Autodesk Fusion 360 part; units mm, degrees
(part 2 of 2)
ref_plane "WorkPlane5" through (0, 0, 7.4) normal (0, 0, 1) x (1, 0, 0) in component "07 Spar fit coupon - 4.1 4.3 4.4 4.5 4.7"
sketch "Label 4.1 digit 0 c sketch" plane through (0, 0, 7.4) normal (0, 0, 1) x (1, 0, 0) in component "07 Spar fit coupon - 4.1 4.3 4.4 4.5 4.7"
  line L0 (9.5, 4.95) -> (9.8, 4.95)
  line L1 (9.8, 4.95) -> (9.8, 5.85)
  line L2 (9.8, 5.85) -> (9.5, 5.85)
  line L3 (9.5, 5.85) -> (9.5, 4.95)
extrude "Label 4.1 digit 0 c" cut sketch "Label 4.1 digit 0 c sketch" along normal blind 1 bodies 7 in component "07 Spar fit coupon - 4.1 4.3 4.4 4.5 4.7"
ref_plane "WorkPlane6" through (0, 0, 7.4) normal (0, 0, 1) x (1, 0, 0) in component "07 Spar fit coupon - 4.1 4.3 4.4 4.5 4.7"
sketch "Label 4.1 dot sketch" plane through (0, 0, 7.4) normal (0, 0, 1) x (1, 0, 0) in component "07 Spar fit coupon - 4.1 4.3 4.4 4.5 4.7"
  line L0 (10.5, 4.5) -> (10.85, 4.5)
  line L1 (10.85, 4.5) -> (10.85, 4.85)
  line L2 (10.85, 4.85) -> (10.5, 4.85)
  line L3 (10.5, 4.85) -> (10.5, 4.5)
extrude "Label 4.1 dot" cut sketch "Label 4.1 dot sketch" along normal blind 1 bodies 7 in component "07 Spar fit coupon - 4.1 4.3 4.4 4.5 4.7"
ref_plane "WorkPlane7" through (0, 0, 7.4) normal (0, 0, 1) x (1, 0, 0) in component "07 Spar fit coupon - 4.1 4.3 4.4 4.5 4.7"
sketch "Label 4.1 digit 2 b sketch" plane through (0, 0, 7.4) normal (0, 0, 1) x (1, 0, 0) in component "07 Spar fit coupon - 4.1 4.3 4.4 4.5 4.7"
  line L0 (14.5, 6.15) -> (14.8, 6.15)
  line L1 (14.8, 6.15) -> (14.8, 7.05)
  line L2 (14.8, 7.05) -> (14.5, 7.05)
  line L3 (14.5, 7.05) -> (14.5, 6.15)
extrude "Label 4.1 digit 2 b" cut sketch "Label 4.1 digit 2 b sketch" along normal blind 1 bodies 7 in component "07 Spar fit coupon - 4.1 4.3 4.4 4.5 4.7"
ref_plane "WorkPlane8" through (0, 0, 7.4) normal (0, 0, 1) x (1, 0, 0) in component "07 Spar fit coupon - 4.1 4.3 4.4 4.5 4.7"
sketch "Label 4.1 digit 2 c sketch" plane through (0, 0, 7.4) normal (0, 0, 1) x (1, 0, 0) in component "07 Spar fit coupon - 4.1 4.3 4.4 4.5 4.7"
  line L0 (14.5, 4.95) -> (14.8, 4.95)
  line L1 (14.8, 4.95) -> (14.8, 5.85)
  line L2 (14.8, 5.85) -> (14.5, 5.85)
  line L3 (14.5, 5.85) -> (14.5, 4.95)
extrude "Label 4.1 digit 2 c" cut sketch "Label 4.1 digit 2 c sketch" along normal blind 1 bodies 7 in component "07 Spar fit coupon - 4.1 4.3 4.4 4.5 4.7"
ref_plane "WorkPlane9" through (-0.05, 0, 0) normal (1, 0, 0) x (0, 1, 0) in component "07 Spar fit coupon - 4.1 4.3 4.4 4.5 4.7"
sketch "Horizontal 4.3 mm fit bore sketch" plane through (-0.05, 0, 0) normal (1, 0, 0) x (0, 0, -1) in component "07 Spar fit coupon - 4.1 4.3 4.4 4.5 4.7"
  circle A0 centre (-3.5, 18) radius 2.15
extrude "Horizontal 4.3 mm fit bore" cut sketch "Horizontal 4.3 mm fit bore sketch" along normal blind 24.1 bodies 7 in component "07 Spar fit coupon - 4.1 4.3 4.4 4.5 4.7"
ref_plane "WorkPlane10" through (0, 0, 7.4) normal (0, 0, 1) x (1, 0, 0) in component "07 Spar fit coupon - 4.1 4.3 4.4 4.5 4.7"
sketch "Label 4.3 digit 0 f sketch" plane through (0, 0, 7.4) normal (0, 0, 1) x (1, 0, 0) in component "07 Spar fit coupon - 4.1 4.3 4.4 4.5 4.7"
  line L0 (8, 18.15) -> (8.3, 18.15)
  line L1 (8.3, 18.15) -> (8.3, 19.05)
  line L2 (8.3, 19.05) -> (8, 19.05)
  line L3 (8, 19.05) -> (8, 18.15)
extrude "Label 4.3 digit 0 f" cut sketch "Label 4.3 digit 0 f sketch" along normal blind 1 bodies 7 in component "07 Spar fit coupon - 4.1 4.3 4.4 4.5 4.7"
ref_plane "WorkPlane11" through (0, 0, 7.4) normal (0, 0, 1) x (1, 0, 0) in component "07 Spar fit coupon - 4.1 4.3 4.4 4.5 4.7"
sketch "Label 4.3 digit 0 g sketch" plane through (0, 0, 7.4) normal (0, 0, 1) x (1, 0, 0) in component "07 Spar fit coupon - 4.1 4.3 4.4 4.5 4.7"
  line L0 (8, 17.85) -> (9.8, 17.85)
  line L1 (9.8, 17.85) -> (9.8, 18.15)
  line L2 (9.8, 18.15) -> (8, 18.15)
  line L3 (8, 18.15) -> (8, 17.85)
extrude "Label 4.3 digit 0 g" cut sketch "Label 4.3 digit 0 g sketch" along normal blind 1 bodies 7 in component "07 Spar fit coupon - 4.1 4.3 4.4 4.5 4.7"
ref_plane "WorkPlane12" through (0, 0, 7.4) normal (0, 0, 1) x (1, 0, 0) in component "07 Spar fit coupon - 4.1 4.3 4.4 4.5 4.7"
sketch "Label 4.3 digit 0 b sketch" plane through (0, 0, 7.4) normal (0, 0, 1) x (1, 0, 0) in component "07 Spar fit coupon - 4.1 4.3 4.4 4.5 4.7"
  line L0 (9.5, 18.15) -> (9.8, 18.15)
  line L1 (9.8, 18.15) -> (9.8, 19.05)
  line L2 (9.8, 19.05) -> (9.5, 19.05)
  line L3 (9.5, 19.05) -> (9.5, 18.15)
extrude "Label 4.3 digit 0 b" cut sketch "Label 4.3 digit 0 b sketch" along normal blind 1 bodies 7 in component "07 Spar fit coupon - 4.1 4.3 4.4 4.5 4.7"
ref_plane "WorkPlane13" through (0, 0, 7.4) normal (0, 0, 1) x (1, 0, 0) in component "07 Spar fit coupon - 4.1 4.3 4.4 4.5 4.7"
sketch "Label 4.3 digit 0 c sketch" plane through (0, 0, 7.4) normal (0, 0, 1) x (1, 0, 0) in component "07 Spar fit coupon - 4.1 4.3 4.4 4.5 4.7"
  line L0 (9.5, 16.95) -> (9.8, 16.95)
  line L1 (9.8, 16.95) -> (9.8, 17.85)
  line L2 (9.8, 17.85) -> (9.5, 17.85)
  line L3 (9.5, 17.85) -> (9.5, 16.95)
extrude "Label 4.3 digit 0 c" cut sketch "Label 4.3 digit 0 c sketch" along normal blind 1 bodies 7 in component "07 Spar fit coupon - 4.1 4.3 4.4 4.5 4.7"
ref_plane "WorkPlane14" through (0, 0, 7.4) normal (0, 0, 1) x (1, 0, 0) in component "07 Spar fit coupon - 4.1 4.3 4.4 4.5 4.7"
sketch "Label 4.3 dot sketch" plane through (0, 0, 7.4) normal (0, 0, 1) x (1, 0, 0) in component "07 Spar fit coupon - 4.1 4.3 4.4 4.5 4.7"
  line L0 (10.5, 16.5) -> (10.85, 16.5)
  line L1 (10.85, 16.5) -> (10.85, 16.85)
  line L2 (10.85, 16.85) -> (10.5, 16.85)
  line L3 (10.5, 16.85) -> (10.5, 16.5)
extrude "Label 4.3 dot" cut sketch "Label 4.3 dot sketch" along normal blind 1 bodies 7 in component "07 Spar fit coupon - 4.1 4.3 4.4 4.5 4.7"
ref_plane "WorkPlane15" through (0, 0, 7.4) normal (0, 0, 1) x (1, 0, 0) in component "07 Spar fit coupon - 4.1 4.3 4.4 4.5 4.7"
sketch "Label 4.3 digit 2 a sketch" plane through (0, 0, 7.4) normal (0, 0, 1) x (1, 0, 0) in component "07 Spar fit coupon - 4.1 4.3 4.4 4.5 4.7"
  line L0 (13, 19.2) -> (14.8, 19.2)
  line L1 (14.8, 19.2) -> (14.8, 19.5)
  line L2 (14.8, 19.5) -> (13, 19.5)
  line L3 (13, 19.5) -> (13, 19.2)
extrude "Label 4.3 digit 2 a" cut sketch "Label 4.3 digit 2 a sketch" along normal blind 1 bodies 7 in component "07 Spar fit coupon - 4.1 4.3 4.4 4.5 4.7"
ref_plane "WorkPlane16" through (0, 0, 7.4) normal (0, 0, 1) x (1, 0, 0) in component "07 Spar fit coupon - 4.1 4.3 4.4 4.5 4.7"
sketch "Label 4.3 digit 2 b sketch" plane through (0, 0, 7.4) normal (0, 0, 1) x (1, 0, 0) in component "07 Spar fit coupon - 4.1 4.3 4.4 4.5 4.7"
  line L0 (14.5, 18.15) -> (14.8, 18.15)
  line L1 (14.8, 18.15) -> (14.8, 19.05)
  line L2 (14.8, 19.05) -> (14.5, 19.05)
  line L3 (14.5, 19.05) -> (14.5, 18.15)
extrude "Label 4.3 digit 2 b" cut sketch "Label 4.3 digit 2 b sketch" along normal blind 1 bodies 7 in component "07 Spar fit coupon - 4.1 4.3 4.4 4.5 4.7"
ref_plane "WorkPlane17" through (0, 0, 7.4) normal (0, 0, 1) x (1, 0, 0) in component "07 Spar fit coupon - 4.1 4.3 4.4 4.5 4.7"
sketch "Label 4.3 digit 2 g sketch" plane through (0, 0, 7.4) normal (0, 0, 1) x (1, 0, 0) in component "07 Spar fit coupon - 4.1 4.3 4.4 4.5 4.7"
  line L0 (13, 17.85) -> (14.8, 17.85)
  line L1 (14.8, 17.85) -> (14.8, 18.15)
  line L2 (14.8, 18.15) -> (13, 18.15)
  line L3 (13, 18.15) -> (13, 17.85)
extrude "Label 4.3 digit 2 g" cut sketch "Label 4.3 digit 2 g sketch" along normal blind 1 bodies 7 in component "07 Spar fit coupon - 4.1 4.3 4.4 4.5 4.7"
ref_plane "WorkPlane18" through (0, 0, 7.4) normal (0, 0, 1) x (1, 0, 0) in component "07 Spar fit coupon - 4.1 4.3 4.4 4.5 4.7"
sketch "Label 4.3 digit 2 c sketch" plane through (0, 0, 7.4) normal (0, 0, 1) x (1, 0, 0) in component "07 Spar fit coupon - 4.1 4.3 4.4 4.5 4.7"
  line L0 (14.5, 16.95) -> (14.8, 16.95)
  line L1 (14.8, 16.95) -> (14.8, 17.85)
  line L2 (14.8, 17.85) -> (14.5, 17.85)
  line L3 (14.5, 17.85) -> (14.5, 16.95)
extrude "Label 4.3 digit 2 c" cut sketch "Label 4.3 digit 2 c sketch" along normal blind 1 bodies 7 in component "07 Spar fit coupon - 4.1 4.3 4.4 4.5 4.7"
ref_plane "WorkPlane19" through (0, 0, 7.4) normal (0, 0, 1) x (1, 0, 0) in component "07 Spar fit coupon - 4.1 4.3 4.4 4.5 4.7"
sketch "Label 4.3 digit 2 d sketch" plane through (0, 0, 7.4) normal (0, 0, 1) x (1, 0, 0) in component "07 Spar fit coupon - 4.1 4.3 4.4 4.5 4.7"
  line L0 (13, 16.5) -> (14.8, 16.5)
  line L1 (14.8, 16.5) -> (14.8, 16.8)
  line L2 (14.8, 16.8) -> (13, 16.8)
  line L3 (13, 16.8) -> (13, 16.5)
extrude "Label 4.3 digit 2 d" cut sketch "Label 4.3 digit 2 d sketch" along normal blind 1 bodies 7 in component "07 Spar fit coupon - 4.1 4.3 4.4 4.5 4.7"
ref_plane "WorkPlane20" through (-0.05, 0, 0) normal (1, 0, 0) x (0, 1, 0) in component "07 Spar fit coupon - 4.1 4.3 4.4 4.5 4.7"
sketch "Horizontal 4.4 mm fit bore sketch" plane through (-0.05, 0, 0) normal (1, 0, 0) x (0, 0, -1) in component "07 Spar fit coupon - 4.1 4.3 4.4 4.5 4.7"
  circle A0 centre (-3.5, 30) radius 2.2
extrude "Horizontal 4.4 mm fit bore" cut sketch "Horizontal 4.4 mm fit bore sketch" along normal blind 24.1 bodies 7 in component "07 Spar fit coupon - 4.1 4.3 4.4 4.5 4.7"
ref_plane "WorkPlane21" through (0, 0, 7.4) normal (0, 0, 1) x (1, 0, 0) in component "07 Spar fit coupon - 4.1 4.3 4.4 4.5 4.7"
sketch "Label 4.4 digit 0 f sketch" plane through (0, 0, 7.4) normal (0, 0, 1) x (1, 0, 0) in component "07 Spar fit coupon - 4.1 4.3 4.4 4.5 4.7"
  line L0 (8, 30.15) -> (8.3, 30.15)
  line L1 (8.3, 30.15) -> (8.3, 31.05)
  line L2 (8.3, 31.05) -> (8, 31.05)
  line L3 (8, 31.05) -> (8, 30.15)
extrude "Label 4.4 digit 0 f" cut sketch "Label 4.4 digit 0 f sketch" along normal blind 1 bodies 7 in component "07 Spar fit coupon - 4.1 4.3 4.4 4.5 4.7"
ref_plane "WorkPlane22" through (0, 0, 7.4) normal (0, 0, 1) x (1, 0, 0) in component "07 Spar fit coupon - 4.1 4.3 4.4 4.5 4.7"
sketch "Label 4.4 digit 0 g sketch" plane through (0, 0, 7.4) normal (0, 0, 1) x (1, 0, 0) in component "07 Spar fit coupon - 4.1 4.3 4.4 4.5 4.7"
  line L0 (8, 29.85) -> (9.8, 29.85)
  line L1 (9.8, 29.85) -> (9.8, 30.15)
  line L2 (9.8, 30.15) -> (8, 30.15)
  line L3 (8, 30.15) -> (8, 29.85)
extrude "Label 4.4 digit 0 g" cut sketch "Label 4.4 digit 0 g sketch" along normal blind 1 bodies 7 in component "07 Spar fit coupon - 4.1 4.3 4.4 4.5 4.7"
ref_plane "WorkPlane23" through (0, 0, 7.4) normal (0, 0, 1) x (1, 0, 0) in component "07 Spar fit coupon - 4.1 4.3 4.4 4.5 4.7"
sketch "Label 4.4 digit 0 b sketch" plane through (0, 0, 7.4) normal (0, 0, 1) x (1, 0, 0) in component "07 Spar fit coupon - 4.1 4.3 4.4 4.5 4.7"
  line L0 (9.5, 30.15) -> (9.8, 30.15)
  line L1 (9.8, 30.15) -> (9.8, 31.05)
  line L2 (9.8, 31.05) -> (9.5, 31.05)
  line L3 (9.5, 31.05) -> (9.5, 30.15)
extrude "Label 4.4 digit 0 b" cut sketch "Label 4.4 digit 0 b sketch" along normal blind 1 bodies 7 in component "07 Spar fit coupon - 4.1 4.3 4.4 4.5 4.7"
ref_plane "WorkPlane24" through (0, 0, 7.4) normal (0, 0, 1) x (1, 0, 0) in component "07 Spar fit coupon - 4.1 4.3 4.4 4.5 4.7"
sketch "Label 4.4 digit 0 c sketch" plane through (0, 0, 7.4) normal (0, 0, 1) x (1, 0, 0) in component "07 Spar fit coupon - 4.1 4.3 4.4 4.5 4.7"
  line L0 (9.5, 28.95) -> (9.8, 28.95)
  line L1 (9.8, 28.95) -> (9.8, 29.85)
  line L2 (9.8, 29.85) -> (9.5, 29.85)
  line L3 (9.5, 29.85) -> (9.5, 28.95)
extrude "Label 4.4 digit 0 c" cut sketch "Label 4.4 digit 0 c sketch" along normal blind 1 bodies 7 in component "07 Spar fit coupon - 4.1 4.3 4.4 4.5 4.7"
ref_plane "WorkPlane25" through (0, 0, 7.4) normal (0, 0, 1) x (1, 0, 0) in component "07 Spar fit coupon - 4.1 4.3 4.4 4.5 4.7"
sketch "Label 4.4 dot sketch" plane through (0, 0, 7.4) normal (0, 0, 1) x (1, 0, 0) in component "07 Spar fit coupon - 4.1 4.3 4.4 4.5 4.7"
  line L0 (10.5, 28.5) -> (10.85, 28.5)
  line L1 (10.85, 28.5) -> (10.85, 28.85)
  line L2 (10.85, 28.85) -> (10.5, 28.85)
  line L3 (10.5, 28.85) -> (10.5, 28.5)
extrude "Label 4.4 dot" cut sketch "Label 4.4 dot sketch" along normal blind 1 bodies 7 in component "07 Spar fit coupon - 4.1 4.3 4.4 4.5 4.7"
ref_plane "WorkPlane26" through (0, 0, 7.4) normal (0, 0, 1) x (1, 0, 0) in component "07 Spar fit coupon - 4.1 4.3 4.4 4.5 4.7"
sketch "Label 4.4 digit 2 f sketch" plane through (0, 0, 7.4) normal (0, 0, 1) x (1, 0, 0) in component "07 Spar fit coupon - 4.1 4.3 4.4 4.5 4.7"
  line L0 (13, 30.15) -> (13.3, 30.15)
  line L1 (13.3, 30.15) -> (13.3, 31.05)
  line L2 (13.3, 31.05) -> (13, 31.05)
  line L3 (13, 31.05) -> (13, 30.15)
extrude "Label 4.4 digit 2 f" cut sketch "Label 4.4 digit 2 f sketch" along normal blind 1 bodies 7 in component "07 Spar fit coupon - 4.1 4.3 4.4 4.5 4.7"
ref_plane "WorkPlane27" through (0, 0, 7.4) normal (0, 0, 1) x (1, 0, 0) in component "07 Spar fit coupon - 4.1 4.3 4.4 4.5 4.7"
sketch "Label 4.4 digit 2 g sketch" plane through (0, 0, 7.4) normal (0, 0, 1) x (1, 0, 0) in component "07 Spar fit coupon - 4.1 4.3 4.4 4.5 4.7"
  line L0 (13, 29.85) -> (14.8, 29.85)
  line L1 (14.8, 29.85) -> (14.8, 30.15)
  line L2 (14.8, 30.15) -> (13, 30.15)
  line L3 (13, 30.15) -> (13, 29.85)
extrude "Label 4.4 digit 2 g" cut sketch "Label 4.4 digit 2 g sketch" along normal blind 1 bodies 7 in component "07 Spar fit coupon - 4.1 4.3 4.4 4.5 4.7"
ref_plane "WorkPlane28" through (0, 0, 7.4) normal (0, 0, 1) x (1, 0, 0) in component "07 Spar fit coupon - 4.1 4.3 4.4 4.5 4.7"
sketch "Label 4.4 digit 2 b sketch" plane through (0, 0, 7.4) normal (0, 0, 1) x (1, 0, 0) in component "07 Spar fit coupon - 4.1 4.3 4.4 4.5 4.7"
  line L0 (14.5, 30.15) -> (14.8, 30.15)
  line L1 (14.8, 30.15) -> (14.8, 31.05)
  line L2 (14.8, 31.05) -> (14.5, 31.05)
  line L3 (14.5, 31.05) -> (14.5, 30.15)
extrude "Label 4.4 digit 2 b" cut sketch "Label 4.4 digit 2 b sketch" along normal blind 1 bodies 7 in component "07 Spar fit coupon - 4.1 4.3 4.4 4.5 4.7"
ref_plane "WorkPlane29" through (0, 0, 7.4) normal (0, 0, 1) x (1, 0, 0) in component "07 Spar fit coupon - 4.1 4.3 4.4 4.5 4.7"
sketch "Label 4.4 digit 2 c sketch" plane through (0, 0, 7.4) normal (0, 0, 1) x (1, 0, 0) in component "07 Spar fit coupon - 4.1 4.3 4.4 4.5 4.7"
  line L0 (14.5, 28.95) -> (14.8, 28.95)
  line L1 (14.8, 28.95) -> (14.8, 29.85)
  line L2 (14.8, 29.85) -> (14.5, 29.85)
  line L3 (14.5, 29.85) -> (14.5, 28.95)
extrude "Label 4.4 digit 2 c" cut sketch "Label 4.4 digit 2 c sketch" along normal blind 1 bodies 7 in component "07 Spar fit coupon - 4.1 4.3 4.4 4.5 4.7"
ref_plane "WorkPlane30" through (-0.05, 0, 0) normal (1, 0, 0) x (0, 1, 0) in component "07 Spar fit coupon - 4.1 4.3 4.4 4.5 4.7"
sketch "Horizontal 4.5 mm fit bore sketch" plane through (-0.05, 0, 0) normal (1, 0, 0) x (0, 0, -1) in component "07 Spar fit coupon - 4.1 4.3 4.4 4.5 4.7"
  circle A0 centre (-3.5, 42) radius 2.25
extrude "Horizontal 4.5 mm fit bore" cut sketch "Horizontal 4.5 mm fit bore sketch" along normal blind 24.1 bodies 7 in component "07 Spar fit coupon - 4.1 4.3 4.4 4.5 4.7"
ref_plane "WorkPlane31" through (0, 0, 7.4) normal (0, 0, 1) x (1, 0, 0) in component "07 Spar fit coupon - 4.1 4.3 4.4 4.5 4.7"
sketch "Label 4.5 digit 0 f sketch" plane through (0, 0, 7.4) normal (0, 0, 1) x (1, 0, 0) in component "07 Spar fit coupon - 4.1 4.3 4.4 4.5 4.7"
  line L0 (8, 42.15) -> (8.3, 42.15)
  line L1 (8.3, 42.15) -> (8.3, 43.05)
  line L2 (8.3, 43.05) -> (8, 43.05)
  line L3 (8, 43.05) -> (8, 42.15)
extrude "Label 4.5 digit 0 f" cut sketch "Label 4.5 digit 0 f sketch" along normal blind 1 bodies 7 in component "07 Spar fit coupon - 4.1 4.3 4.4 4.5 4.7"
ref_plane "WorkPlane32" through (0, 0, 7.4) normal (0, 0, 1) x (1, 0, 0) in component "07 Spar fit coupon - 4.1 4.3 4.4 4.5 4.7"
sketch "Label 4.5 digit 0 g sketch" plane through (0, 0, 7.4) normal (0, 0, 1) x (1, 0, 0) in component "07 Spar fit coupon - 4.1 4.3 4.4 4.5 4.7"
  line L0 (8, 41.85) -> (9.8, 41.85)
  line L1 (9.8, 41.85) -> (9.8, 42.15)
  line L2 (9.8, 42.15) -> (8, 42.15)
  line L3 (8, 42.15) -> (8, 41.85)
extrude "Label 4.5 digit 0 g" cut sketch "Label 4.5 digit 0 g sketch" along normal blind 1 bodies 7 in component "07 Spar fit coupon - 4.1 4.3 4.4 4.5 4.7"
ref_plane "WorkPlane33" through (0, 0, 7.4) normal (0, 0, 1) x (1, 0, 0) in component "07 Spar fit coupon - 4.1 4.3 4.4 4.5 4.7"
sketch "Label 4.5 digit 0 b sketch" plane through (0, 0, 7.4) normal (0, 0, 1) x (1, 0, 0) in component "07 Spar fit coupon - 4.1 4.3 4.4 4.5 4.7"
  line L0 (9.5, 42.15) -> (9.8, 42.15)
  line L1 (9.8, 42.15) -> (9.8, 43.05)
  line L2 (9.8, 43.05) -> (9.5, 43.05)
  line L3 (9.5, 43.05) -> (9.5, 42.15)
extrude "Label 4.5 digit 0 b" cut sketch "Label 4.5 digit 0 b sketch" along normal blind 1 bodies 7 in component "07 Spar fit coupon - 4.1 4.3 4.4 4.5 4.7"
ref_plane "WorkPlane34" through (0, 0, 7.4) normal (0, 0, 1) x (1, 0, 0) in component "07 Spar fit coupon - 4.1 4.3 4.4 4.5 4.7"
sketch "Label 4.5 digit 0 c sketch" plane through (0, 0, 7.4) normal (0, 0, 1) x (1, 0, 0) in component "07 Spar fit coupon - 4.1 4.3 4.4 4.5 4.7"
  line L0 (9.5, 40.95) -> (9.8, 40.95)
  line L1 (9.8, 40.95) -> (9.8, 41.85)
  line L2 (9.8, 41.85) -> (9.5, 41.85)
  line L3 (9.5, 41.85) -> (9.5, 40.95)
extrude "Label 4.5 digit 0 c" cut sketch "Label 4.5 digit 0 c sketch" along normal blind 1 bodies 7 in component "07 Spar fit coupon - 4.1 4.3 4.4 4.5 4.7"
ref_plane "WorkPlane35" through (0, 0, 7.4) normal (0, 0, 1) x (1, 0, 0) in component "07 Spar fit coupon - 4.1 4.3 4.4 4.5 4.7"
sketch "Label 4.5 dot sketch" plane through (0, 0, 7.4) normal (0, 0, 1) x (1, 0, 0) in component "07 Spar fit coupon - 4.1 4.3 4.4 4.5 4.7"
  line L0 (10.5, 40.5) -> (10.85, 40.5)
  line L1 (10.85, 40.5) -> (10.85, 40.85)
  line L2 (10.85, 40.85) -> (10.5, 40.85)
  line L3 (10.5, 40.85) -> (10.5, 40.5)
extrude "Label 4.5 dot" cut sketch "Label 4.5 dot sketch" along normal blind 1 bodies 7 in component "07 Spar fit coupon - 4.1 4.3 4.4 4.5 4.7"
ref_plane "WorkPlane36" through (0, 0, 7.4) normal (0, 0, 1) x (1, 0, 0) in component "07 Spar fit coupon - 4.1 4.3 4.4 4.5 4.7"
sketch "Label 4.5 digit 2 a sketch" plane through (0, 0, 7.4) normal (0, 0, 1) x (1, 0, 0) in component "07 Spar fit coupon - 4.1 4.3 4.4 4.5 4.7"
  line L0 (13, 43.2) -> (14.8, 43.2)
  line L1 (14.8, 43.2) -> (14.8, 43.5)
  line L2 (14.8, 43.5) -> (13, 43.5)
  line L3 (13, 43.5) -> (13, 43.2)
extrude "Label 4.5 digit 2 a" cut sketch "Label 4.5 digit 2 a sketch" along normal blind 1 bodies 7 in component "07 Spar fit coupon - 4.1 4.3 4.4 4.5 4.7"
ref_plane "WorkPlane37" through (0, 0, 7.4) normal (0, 0, 1) x (1, 0, 0) in component "07 Spar fit coupon - 4.1 4.3 4.4 4.5 4.7"
sketch "Label 4.5 digit 2 f sketch" plane through (0, 0, 7.4) normal (0, 0, 1) x (1, 0, 0) in component "07 Spar fit coupon - 4.1 4.3 4.4 4.5 4.7"
  line L0 (13, 42.15) -> (13.3, 42.15)
  line L1 (13.3, 42.15) -> (13.3, 43.05)
  line L2 (13.3, 43.05) -> (13, 43.05)
  line L3 (13, 43.05) -> (13, 42.15)
extrude "Label 4.5 digit 2 f" cut sketch "Label 4.5 digit 2 f sketch" along normal blind 1 bodies 7 in component "07 Spar fit coupon - 4.1 4.3 4.4 4.5 4.7"
ref_plane "WorkPlane38" through (0, 0, 7.4) normal (0, 0, 1) x (1, 0, 0) in component "07 Spar fit coupon - 4.1 4.3 4.4 4.5 4.7"
sketch "Label 4.5 digit 2 g sketch" plane through (0, 0, 7.4) normal (0, 0, 1) x (1, 0, 0) in component "07 Spar fit coupon - 4.1 4.3 4.4 4.5 4.7"
  line L0 (13, 41.85) -> (14.8, 41.85)
  line L1 (14.8, 41.85) -> (14.8, 42.15)
  line L2 (14.8, 42.15) -> (13, 42.15)
  line L3 (13, 42.15) -> (13, 41.85)
extrude "Label 4.5 digit 2 g" cut sketch "Label 4.5 digit 2 g sketch" along normal blind 1 bodies 7 in component "07 Spar fit coupon - 4.1 4.3 4.4 4.5 4.7"
ref_plane "WorkPlane39" through (0, 0, 7.4) normal (0, 0, 1) x (1, 0, 0) in component "07 Spar fit coupon - 4.1 4.3 4.4 4.5 4.7"
sketch "Label 4.5 digit 2 c sketch" plane through (0, 0, 7.4) normal (0, 0, 1) x (1, 0, 0) in component "07 Spar fit coupon - 4.1 4.3 4.4 4.5 4.7"
  line L0 (14.5, 40.95) -> (14.8, 40.95)
  line L1 (14.8, 40.95) -> (14.8, 41.85)
  line L2 (14.8, 41.85) -> (14.5, 41.85)
  line L3 (14.5, 41.85) -> (14.5, 40.95)
extrude "Label 4.5 digit 2 c" cut sketch "Label 4.5 digit 2 c sketch" along normal blind 1 bodies 7 in component "07 Spar fit coupon - 4.1 4.3 4.4 4.5 4.7"
ref_plane "WorkPlane40" through (0, 0, 7.4) normal (0, 0, 1) x (1, 0, 0) in component "07 Spar fit coupon - 4.1 4.3 4.4 4.5 4.7"
sketch "Label 4.5 digit 2 d sketch" plane through (0, 0, 7.4) normal (0, 0, 1) x (1, 0, 0) in component "07 Spar fit coupon - 4.1 4.3 4.4 4.5 4.7"
  line L0 (13, 40.5) -> (14.8, 40.5)
  line L1 (14.8, 40.5) -> (14.8, 40.8)
  line L2 (14.8, 40.8) -> (13, 40.8)
  line L3 (13, 40.8) -> (13, 40.5)
extrude "Label 4.5 digit 2 d" cut sketch "Label 4.5 digit 2 d sketch" along normal blind 1 bodies 7 in component "07 Spar fit coupon - 4.1 4.3 4.4 4.5 4.7"
ref_plane "WorkPlane41" through (-0.05, 0, 0) normal (1, 0, 0) x (0, 1, 0) in component "07 Spar fit coupon - 4.1 4.3 4.4 4.5 4.7"
sketch "Horizontal 4.7 mm fit bore sketch" plane through (-0.05, 0, 0) normal (1, 0, 0) x (0, 0, -1) in component "07 Spar fit coupon - 4.1 4.3 4.4 4.5 4.7"
  circle A0 centre (-3.5, 54) radius 2.35
extrude "Horizontal 4.7 mm fit bore" cut sketch "Horizontal 4.7 mm fit bore sketch" along normal blind 24.1 bodies 7 in component "07 Spar fit coupon - 4.1 4.3 4.4 4.5 4.7"
ref_plane "WorkPlane42" through (0, 0, 7.4) normal (0, 0, 1) x (1, 0, 0) in component "07 Spar fit coupon - 4.1 4.3 4.4 4.5 4.7"
sketch "Label 4.7 digit 0 f sketch" plane through (0, 0, 7.4) normal (0, 0, 1) x (1, 0, 0) in component "07 Spar fit coupon - 4.1 4.3 4.4 4.5 4.7"
  line L0 (8, 54.15) -> (8.3, 54.15)
  line L1 (8.3, 54.15) -> (8.3, 55.05)
  line L2 (8.3, 55.05) -> (8, 55.05)
  line L3 (8, 55.05) -> (8, 54.15)
extrude "Label 4.7 digit 0 f" cut sketch "Label 4.7 digit 0 f sketch" along normal blind 1 bodies 7 in component "07 Spar fit coupon - 4.1 4.3 4.4 4.5 4.7"
ref_plane "WorkPlane43" through (0, 0, 7.4) normal (0, 0, 1) x (1, 0, 0) in component "07 Spar fit coupon - 4.1 4.3 4.4 4.5 4.7"
sketch "Label 4.7 digit 0 g sketch" plane through (0, 0, 7.4) normal (0, 0, 1) x (1, 0, 0) in component "07 Spar fit coupon - 4.1 4.3 4.4 4.5 4.7"
  line L0 (8, 53.85) -> (9.8, 53.85)
  line L1 (9.8, 53.85) -> (9.8, 54.15)
  line L2 (9.8, 54.15) -> (8, 54.15)
  line L3 (8, 54.15) -> (8, 53.85)
extrude "Label 4.7 digit 0 g" cut sketch "Label 4.7 digit 0 g sketch" along normal blind 1 bodies 7 in component "07 Spar fit coupon - 4.1 4.3 4.4 4.5 4.7"
ref_plane "WorkPlane44" through (0, 0, 7.4) normal (0, 0, 1) x (1, 0, 0) in component "07 Spar fit coupon - 4.1 4.3 4.4 4.5 4.7"
sketch "Label 4.7 digit 0 b sketch" plane through (0, 0, 7.4) normal (0, 0, 1) x (1, 0, 0) in component "07 Spar fit coupon - 4.1 4.3 4.4 4.5 4.7"
  line L0 (9.5, 54.15) -> (9.8, 54.15)
  line L1 (9.8, 54.15) -> (9.8, 55.05)
  line L2 (9.8, 55.05) -> (9.5, 55.05)
  line L3 (9.5, 55.05) -> (9.5, 54.15)
extrude "Label 4.7 digit 0 b" cut sketch "Label 4.7 digit 0 b sketch" along normal blind 1 bodies 7 in component "07 Spar fit coupon - 4.1 4.3 4.4 4.5 4.7"
ref_plane "WorkPlane45" through (0, 0, 7.4) normal (0, 0, 1) x (1, 0, 0) in component "07 Spar fit coupon - 4.1 4.3 4.4 4.5 4.7"
sketch "Label 4.7 digit 0 c sketch" plane through (0, 0, 7.4) normal (0, 0, 1) x (1, 0, 0) in component "07 Spar fit coupon - 4.1 4.3 4.4 4.5 4.7"
  line L0 (9.5, 52.95) -> (9.8, 52.95)
  line L1 (9.8, 52.95) -> (9.8, 53.85)
  line L2 (9.8, 53.85) -> (9.5, 53.85)
  line L3 (9.5, 53.85) -> (9.5, 52.95)
extrude "Label 4.7 digit 0 c" cut sketch "Label 4.7 digit 0 c sketch" along normal blind 1 bodies 7 in component "07 Spar fit coupon - 4.1 4.3 4.4 4.5 4.7"
ref_plane "WorkPlane46" through (0, 0, 7.4) normal (0, 0, 1) x (1, 0, 0) in component "07 Spar fit coupon - 4.1 4.3 4.4 4.5 4.7"
sketch "Label 4.7 dot sketch" plane through (0, 0, 7.4) normal (0, 0, 1) x (1, 0, 0) in component "07 Spar fit coupon - 4.1 4.3 4.4 4.5 4.7"
  line L0 (10.5, 52.5) -> (10.85, 52.5)
  line L1 (10.85, 52.5) -> (10.85, 52.85)
  line L2 (10.85, 52.85) -> (10.5, 52.85)
  line L3 (10.5, 52.85) -> (10.5, 52.5)
extrude "Label 4.7 dot" cut sketch "Label 4.7 dot sketch" along normal blind 1 bodies 7 in component "07 Spar fit coupon - 4.1 4.3 4.4 4.5 4.7"
ref_plane "WorkPlane47" through (0, 0, 7.4) normal (0, 0, 1) x (1, 0, 0) in component "07 Spar fit coupon - 4.1 4.3 4.4 4.5 4.7"
sketch "Label 4.7 digit 2 a sketch" plane through (0, 0, 7.4) normal (0, 0, 1) x (1, 0, 0) in component "07 Spar fit coupon - 4.1 4.3 4.4 4.5 4.7"
  line L0 (13, 55.2) -> (14.8, 55.2)
  line L1 (14.8, 55.2) -> (14.8, 55.5)
  line L2 (14.8, 55.5) -> (13, 55.5)
  line L3 (13, 55.5) -> (13, 55.2)
extrude "Label 4.7 digit 2 a" cut sketch "Label 4.7 digit 2 a sketch" along normal blind 1 bodies 7 in component "07 Spar fit coupon - 4.1 4.3 4.4 4.5 4.7"
ref_plane "WorkPlane48" through (0, 0, 7.4) normal (0, 0, 1) x (1, 0, 0) in component "07 Spar fit coupon - 4.1 4.3 4.4 4.5 4.7"
sketch "Label 4.7 digit 2 b sketch" plane through (0, 0, 7.4) normal (0, 0, 1) x (1, 0, 0) in component "07 Spar fit coupon - 4.1 4.3 4.4 4.5 4.7"
  line L0 (14.5, 54.15) -> (14.8, 54.15)
  line L1 (14.8, 54.15) -> (14.8, 55.05)
  line L2 (14.8, 55.05) -> (14.5, 55.05)
  line L3 (14.5, 55.05) -> (14.5, 54.15)
extrude "Label 4.7 digit 2 b" cut sketch "Label 4.7 digit 2 b sketch" along normal blind 1 bodies 7 in component "07 Spar fit coupon - 4.1 4.3 4.4 4.5 4.7"
ref_plane "WorkPlane49" through (0, 0, 7.4) normal (0, 0, 1) x (1, 0, 0) in component "07 Spar fit coupon - 4.1 4.3 4.4 4.5 4.7"
sketch "Label 4.7 digit 2 c sketch" plane through (0, 0, 7.4) normal (0, 0, 1) x (1, 0, 0) in component "07 Spar fit coupon - 4.1 4.3 4.4 4.5 4.7"
  line L0 (14.5, 52.95) -> (14.8, 52.95)
  line L1 (14.8, 52.95) -> (14.8, 53.85)
  line L2 (14.8, 53.85) -> (14.5, 53.85)
  line L3 (14.5, 53.85) -> (14.5, 52.95)
extrude "Label 4.7 digit 2 c" cut sketch "Label 4.7 digit 2 c sketch" along normal blind 1 bodies 7 in component "07 Spar fit coupon - 4.1 4.3 4.4 4.5 4.7"
ref_plane "WorkPlane1" through (0, 0, 50.65) normal (0, 0, 1) x (1, 0, 0) in component "REFERENCE ONLY - bamboo, example bar cell, sensor envelopes"
sketch "EXAMPLE 60mm bar cell - no assumed screw pattern sketch" plane through (0, 0, 50.65) normal (0, 0, 1) x (1, 0, 0) in component "REFERENCE ONLY - bamboo, example bar cell, sensor envelopes"
  line L0 (140, -6.35) -> (200, -6.35)
  line L1 (200, -6.35) -> (200, 6.35)
  line L2 (200, 6.35) -> (140, 6.35)
  line L3 (140, 6.35) -> (140, -6.35)
extrude "EXAMPLE 60mm bar cell - no assumed screw pattern" add sketch "EXAMPLE 60mm bar cell - no assumed screw pattern sketch" along normal blind 12.7 separate body makes body 8 in component "REFERENCE ONLY - bamboo, example bar cell, sensor envelopes"
ref_plane "WorkPlane2" through (-6, 0, 0) normal (1, 0, 0) x (0, 1, 0) in component "REFERENCE ONLY - bamboo, example bar cell, sensor envelopes"
sketch "4mm bamboo reference -18 sketch" plane through (-6, 0, 0) normal (1, 0, 0) x (0, 0, -1) in component "REFERENCE ONLY - bamboo, example bar cell, sensor envelopes"
  circle A0 centre (-19.4, -18) radius 2
extrude "4mm bamboo reference -18" add sketch "4mm bamboo reference -18 sketch" along normal blind 132 separate body makes body 9 in component "REFERENCE ONLY - bamboo, example bar cell, sensor envelopes"
ref_plane "WorkPlane3" through (-6, 0, 0) normal (1, 0, 0) x (0, 1, 0) in component "REFERENCE ONLY - bamboo, example bar cell, sensor envelopes"
sketch "4mm bamboo reference 18 sketch" plane through (-6, 0, 0) normal (1, 0, 0) x (0, 0, -1) in component "REFERENCE ONLY - bamboo, example bar cell, sensor envelopes"
  circle A0 centre (-19.4, 18) radius 2
extrude "4mm bamboo reference 18" add sketch "4mm bamboo reference 18 sketch" along normal blind 132 separate body makes body 10 in component "REFERENCE ONLY - bamboo, example bar cell, sensor envelopes"
ref_plane "WorkPlane4" through (0, 0, 23.2) normal (0, 0, 1) x (1, 0, 0) in component "REFERENCE ONLY - bamboo, example bar cell, sensor envelopes"
sketch "MPU board envelope sketch" plane through (0, 0, 23.2) normal (0, 0, 1) x (1, 0, 0) in component "REFERENCE ONLY - bamboo, example bar cell, sensor envelopes"
  line L0 (75, -10) -> (97, -10)
  line L1 (97, -10) -> (97, 10)
  line L2 (97, 10) -> (75, 10)
  line L3 (75, 10) -> (75, -10)
extrude "MPU board envelope" add sketch "MPU board envelope sketch" along normal blind 1.6 separate body makes body 11 in component "REFERENCE ONLY - bamboo, example bar cell, sensor envelopes"
ref_plane "WorkPlane5" through (0, 0, 17.8) normal (0, 0, 1) x (1, 0, 0) in component "REFERENCE ONLY - bamboo, example bar cell, sensor envelopes"
sketch "Gauge backing envelope sketch" plane through (0, 0, 17.8) normal (0, 0, 1) x (1, 0, 0) in component "REFERENCE ONLY - bamboo, example bar cell, sensor envelopes"
  line L0 (33, -3) -> (43, -3)
  line L1 (43, -3) -> (43, 3)
  line L2 (43, 3) -> (33, 3)
  line L3 (33, 3) -> (33, -3)
extrude "Gauge backing envelope" add sketch "Gauge backing envelope sketch" along normal blind 0.2 separate body makes body 12 in component "REFERENCE ONLY - bamboo, example bar cell, sensor envelopes"
component "01 Flexible wing - short 4.5mm spar guides" placed x (1, 0, 0) y (0, 1, 0) z (0, 0, 1) at (0, 0, 16)
component "02 Root base - bench clamp" placed x (1, 0, 0) y (0, 1, 0) z (0, 0, 1) at (0, 0, 0)
component "03 Root cap" placed x (1, 0, 0) y (0, 1, 0) z (0, 0, 1) at (0, 0, 24)
component "04 Tip adapter - adjustable glue mount rails" placed x (1, 0, 0) y (0, 1, 0) z (0, 0, 1) at (112, 0, 22.95)
component "05 Fixed end glue pedestal" placed x (1, 0, 0) y (0, 1, 0) z (0, 0, 1) at (145, 0, 28.95)
component "06 Free end glue hanger" placed x (1, 0, 0) y (0, 1, 0) z (0, 0, 1) at (195, 0, 38.95)
component "07 Spar fit coupon - 4.1 4.3 4.4 4.5 4.7" placed x (1, 0, 0) y (0, 1, 0) z (0, 0, 1) at (-65, 85, 0)
component "REFERENCE ONLY - bamboo, example bar cell, sensor envelopes" placed x (1, 0, 0) y (0, 1, 0) z (0, 0, 1) at (0, 0, 0)
equation "sparDiameter = 4 mm" comment "Nominal bamboo diameter; choose clearance with fit coupon"
equation "sparClearance = 0.5 mm" comment "Diametral clearance; 4.5 mm coupon fit selected by user"
equation "sparBore = sparDiameter + sparClearance" comment "Drives BOTH native spar channel sketches"
equation "m3Clearance = 3.4 mm" comment "Root registration and tip adapter holes"
equation "m4Clearance = 4.4 mm" comment "Root clamp bolt holes"
equation "rootThickness = 8 mm" comment "Root tongue extrusion; reposition cap if changed"
equation "gaugeBeamThickness = 1.8 mm" comment "Continuous flexing gauge strip; physical response needs testing"
equation "mpuPadThickness = 7.2 mm" comment "Raised pad clears the 6.95 mm rib tops"
equation "d9 = rootThickness"
equation "d11 = gaugeBeamThickness"
equation "d99 = mpuPadThickness"
equation "d103 = sparBore"
equation "d108 = sparBore"
equation "d113 = m3Clearance"
equation "d118 = m3Clearance"
equation "d123 = m3Clearance"
equation "d128 = m3Clearance"
equation "d133 = m3Clearance"
equation "d138 = m3Clearance"
equation "d173 = m4Clearance"
equation "d182 = m4Clearance"
equation "d191 = m4Clearance"
equation "d200 = m4Clearance"
equation "d219 = m4Clearance"
equation "d224 = m4Clearance"
equation "d229 = m4Clearance"
equation "d234 = m4Clearance"
equation "d241 = m3Clearance"
equation "d246 = m3Clearance"
equation "d251 = m3Clearance"
equation "d256 = m3Clearance"
equation "d295 = m3Clearance"
equation "d300 = m3Clearance"
equation "d305 = m3Clearance"
equation "d310 = m3Clearance"
named bodies: "wing - printable solid", "root_base - printable solid", "root_cap - printable solid", "tip_adapter - printable solid", "cell_spacer - printable solid", "load_hanger - printable solid", "spar_fit_coupon - printable solid"
